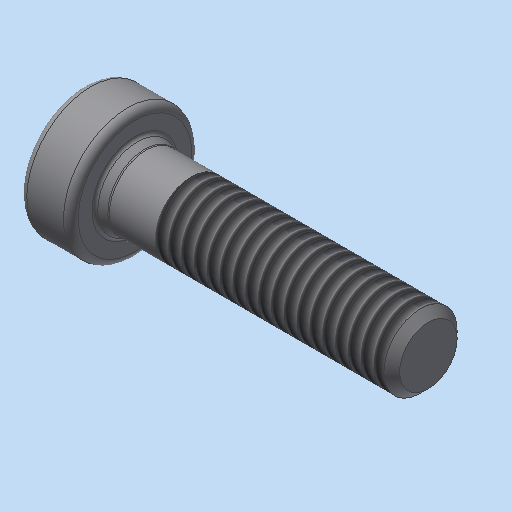
# Autodesk Inventor part: Zylinderschraube_DIN_6912___M4x16
Saved by Autodesk Inventor 2023.3 (Build 273359000, 359)
## iProperties
Shininess: 64.0
Length Units: 11269
Angle Units: 11279
Time Units: 11290
Mass Units: 11283
Length Display Precision: 3
Angle Display Precision: 2
Compacted: True
Part Number: Zylinderschraube_DIN_6912___M4x16
Document SubType Name: Modeling
Created: 2004-04-02
Material: xStahl_AnP_Dummymaterial
Description: =<RBPARTNOTITLE2>
Vendor: NORM8
Designer: S.Riedelsheimer
Manufacturer: Standard
Standards Organization: Custom
Density: 7.85 g/cm^3
Appearance: RGB(178,178,178)
DOC_ID: 5 F45 Zylinderschraube_DIN_6912___M4x16
GAIN_REFID: 20__Zylinderschraube_DIN_6912___M4x16:81C07
Control State: 0
Master: False
Checked Out: False
CNS_NB: Zylinderschraube DIN 6912 - M4x16
CNS_NN: DIN 6912
CNS_NT: Zylinderschraube mit Innensechskant, niedriger Kopf, mit Schluesselfuehrung
CNS_NBSYN: Zylinderschraube DIN 6912 - $NENN.
CNS_LINA: Zylinderschraube DIN 6912 - M4x16
CNS_NENN: M4x16
CNS_D: 4.000
CNS_D3: 3.141
CNS_P: 0.700
CNS_L: 16.000
CNS_S: 3.000
CNS_T: 1.600
CNS_LS: 1.400
CNS_LG: 3.500
CNS_DK: 7.000
CNS_K: 2.800
CNS_DA: 4.700
CNS_DW: 6.200
CNS_DH: 2.000
CNS_R: 0.200
CNS_V: 0.400
CNS_T1: 3.300
CNS_F: 0.600
CNS_KT: L
PSOL_IDENT_0: {C:\partsolutions8\data\23d-libs\bosch_bamberg\schrauben\zylinderschrauben\din_6912.prj},169 {M=Nenn
PSOL_IDENT_1: gewinde},{VTYP=3D},{NB=Zylinderschraube DIN 6912 - M4x16},{NN=DIN 6912},{DATE=26.11.2003},{GEOMDATE=
PSOL_IDENT_2: 26.11.2003},{VERSION=v1},{LINEID=30},{LINESUBID=-1},{WBVAR=}  {NB=Zylinderschraube DIN 6912 - M4x16}
PSOL_IDENT_3: ,{LINA=Zylinderschraube DIN 6912 - M4x16},{KT=L},{IDNR=},{NENN=M4x16},{D=4.000},{D3=3.141},{P=0.700}
PSOL_IDENT_4: ,{L=16.000},{S=3.000},{T=1.600},{LS=1.400},{LG=3.500},{DK=7.000},{K=2.800},{DA=4.700},{DW=6.200},{DH
PSOL_IDENT_5: =2.000},{R=0.200},{V=0.400},{T1=3.300},{F=0.600}
DEF_STKID: T20532
Bezeichnung1: Zylinderschraube DIN 6912 - M4x16
Bezeichnung2: Zylinderschraube mit Innensechskant, ni
RBPARTNOTITLE2: Zylinderschraube mit Innensechskant, niedriger Kopf
RBPARTMADEOF: DIN 6912 - M4x16
Density: 0.0
Volumn: 0.0
Area: 0.0
PropertySet Name: Model Information
Title: Zylinderschraube DIN 6912 - M4x16
Author: S.Riedelsheimer
Keywords: =<RBPARTMADEOF>
Revision Number: 01
Autodesk Inventor part; units mm, degrees
sketch "Sketch_1" plane through (0, 0, 0) normal (0, 1, 0) x (-1, 0, 0)
  line L0 (2.8, 0) -> (-16, 0)
  line L1 (-16, 0) -> (-16, 1.5705)
  line L2 (-16, 1.5705) -> (-15.5705, 2)
  line L3 (-15.5705, 2) -> (-0.6, 2)
  arc A0 (-0.6, 2) -> (-0.5298, 2.0127) centre (-0.6, 2.2) ccw
  line L4 (-0.5298, 2.0127) -> (-0.1298, 2.1627)
  arc A1 (-0.1298, 2.1627) -> (0, 2.35) centre (-0.2, 2.35) ccw
  line L5 (0, 2.35) -> (0, 3.1)
  arc A2 (0.4, 3.5) -> (0, 3.1) centre (0.4, 3.1) ccw
  line L6 (0.4, 3.5) -> (2.4, 3.5)
  arc A3 (2.8, 3.1) -> (2.4, 3.5) centre (2.4, 3.1) ccw
  line L7 (2.8, 3.1) -> (2.8, 1.7321)
  line L8 (2.8, 1.7321) -> (2.5679, 1.5)
  line L9 (2.5679, 1.5) -> (1.2, 1.5)
  line L10 (1.2, 1.5) -> (0.9113, 1)
  line L11 (0.9113, 1) -> (-0.5, 1)
  line L12 (-0.5, 1) -> (-1.0774, 0)
  line L13 (-1.0774, 0) -> (-16, 0)
  constraints: 28 end point, 8 point on circle, 4 centre point
revolve "Drehung1" add sketch "Sketch_1" angle 360 about axis through (-2.8, 0, 0) along (-1, 0, 0)
thread "Gewinde1" size "M4x0.7" class "6g" standard "ANSI Metric M Profile" length 12.5
sketch "Sketch_2" plane through (-2.8, 0, 0) normal (-1, 0, 0) x (0, 0, 1)
  line L0 (-1.5, 0.866) -> (-1.5, -0.866)
  line L1 (-1.5, -0.866) -> (0, -1.7321)
  line L2 (0, -1.7321) -> (1.5, -0.866)
  line L3 (1.5, -0.866) -> (1.5, 0.866)
  line L4 (1.5, 0.866) -> (0, 1.7321)
  line L5 (0, 1.7321) -> (-1.5, 0.866)
  constraints: 12 end point
extrude "Extrusion1" cut sketch "Sketch_2" along normal mid plane 3.2
ref_plane "IP1_XY" through (0, 0, 0) normal (1, 0, 0) x (0, 0, -1)
ref_plane "IP1_YZ" through (0, 0, 0) normal (0, 0, -1) x (0, 1, 0)
ref_plane "IP2_XY" through (-2.8, 0, 0) normal (1, 0, 0) x (0, 0, -1)
ref_plane "IP2_YZ" through (-2.8, 0, 0) normal (0, 0, -1) x (0, 1, 0)
ref_plane "IP3_XY" through (16, 0, 0) normal (1, 0, 0) x (0, 0, -1)
ref_plane "IP3_YZ" through (16, 0, 0) normal (0, 0, -1) x (0, 1, 0)
